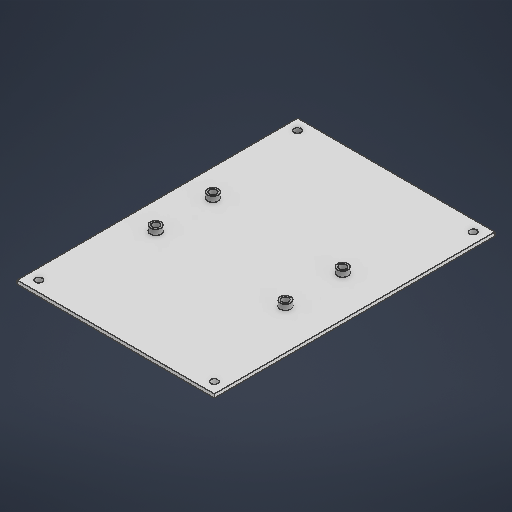
# Autodesk Inventor part: bottom
Saved by Autodesk Inventor 2026.2 (Build 302298010, 298A)
## iProperties
Created: 2026-05-12
Part Number: bottom
Material: 일반
Document SubType Name: Modeling
Designer: work
Density: 1 g/cm^3
Appearance: 기본값
Author: work
Autodesk Inventor part; units mm, degrees
ref_plane "YZ Plane" through (0, 0, 0) normal (1, 0, 0) x (0, 1, 0)
ref_plane "XZ Plane" through (0, 0, 0) normal (0, 1, 0) x (-1, 0, 0)
ref_plane "XY Plane" through (0, 0, 0) normal (0, 0, 1) x (1, 0, 0)
sketch "스케치1" plane through (0, 0, 0) normal (0, 1, 0) x (-1, 0, 0)
  line L0 (0, 0) -> (110, 0)
  line L1 (110, 0) -> (110, -156.5)
  line L2 (110, -156.5) -> (0, -156.5)
  line L3 (0, -156.5) -> (0, 0)
  line L4 (110, -78.25) -> (0, -78.25) construction
  line L5 (55, 0) -> (55, -156.5) construction
  line L6 (6, -6) -> (104, -6) construction
  line L7 (104, -6) -> (104, -150.5) construction
  line L8 (104, -150.5) -> (6, -150.5) construction
  line L9 (6, -150.5) -> (6, -6) construction
  line L10 (6, -6) -> (104, -150.5) construction
  line L11 (104, -6) -> (6, -150.5) construction
  line L12 (18.8, -43.25) -> (98.8, -43.25) construction
  line L13 (98.8, -43.25) -> (98.8, -113.25) construction
  line L14 (98.8, -113.25) -> (18.8, -113.25) construction
  line L15 (18.8, -113.25) -> (18.8, -43.25) construction
  line L16 (18.8, -43.25) -> (98.8, -113.25) construction
  line L17 (98.8, -43.25) -> (18.8, -113.25) construction
  line L18 (22.6, -62.25) -> (95, -62.25) construction
  line L19 (95, -62.25) -> (95, -94.25) construction
  line L20 (95, -94.25) -> (22.6, -94.25) construction
  line L21 (22.6, -94.25) -> (22.6, -62.25) construction
  line L22 (22.6, -62.25) -> (95, -94.25) construction
  line L23 (95, -62.25) -> (22.6, -94.25) construction
  circle A0 centre (95, -62.25) radius 2
  circle A1 centre (95, -94.25) radius 2
  circle A2 centre (22.6, -62.25) radius 2
  circle A3 centre (22.6, -94.25) radius 2
  circle A4 centre (6, -150.5) radius 2
  circle A5 centre (6, -6) radius 2
  circle A6 centre (104, -6) radius 2
  circle A7 centre (104, -150.5) radius 2
  point P0 (55, -78.25)
  point P1 (58.8, -78.25)
  dimension "d0" = 80
  dimension "d1" = 70
  dimension "d2" = 72.4
  dimension "d3" = 32
  dimension "d4" = 4
  dimension "d5" = 4
  dimension "d6" = 4
  dimension "d7" = 4
  dimension "d8" = 98
  dimension "d9" = 144.5
  dimension "d10" = 6
  dimension "d11" = 6
  dimension "d12" = 15
  dimension "d13" = 4
  dimension "d14" = 4
  dimension "d15" = 4
  dimension "d16" = 4
  constraints: 48 end point, 11 midpoint, 8 centre point, 8 coincident, 8 parallel, 4 horizontal, 4 perpendicular, 1 point on line
  measures "d0" distance of L13.end L14.end
  measures "d1" distance of L12.end L13.end
  measures "d2" distance of L19.end L20.end
  measures "d3" distance of L18.end L19.end
  measures "d4" diameter of A0
  measures "d5" diameter of A1
  measures "d6" diameter of A2
  measures "d7" diameter of A3
  measures "d8" distance between parallel lines of L9 L7
  measures "d9" distance of L8.end L6.start
  measures "d10" distance between parallel lines of L0 L6
  measures "d11" distance between parallel lines of L1 L7
  measures "d12" distance between parallel lines of L1 L19
  measures "d13" diameter of A4
  measures "d14" diameter of A5
  measures "d15" diameter of A6
  measures "d16" diameter of A7
extrude "돌출1" add sketch "스케치1" along normal blind 3
sketch "스케치2" plane through (0, 3, 0) normal (0, 1, 0) x (1, 0, 0)
  line L0 (0, 156.5) -> (-110, 156.5) projected
  line L1 (-110, 156.5) -> (-110, 0) projected
  line L2 (-110, 0) -> (0, 0) projected
  line L3 (0, 0) -> (0, 156.5) projected
  circle A0 centre (-104, 150.5) radius 2 projected
  circle A1 centre (-104, 6) radius 2 projected
  circle A2 centre (-6, 6) radius 2 projected
  circle A3 centre (-6, 150.5) radius 2 projected
  circle A4 centre (-22.6, 94.25) radius 2 projected
  circle A5 centre (-22.6, 62.25) radius 2 projected
  circle A6 centre (-95, 94.25) radius 2 projected
  circle A7 centre (-95, 62.25) radius 2 projected
  circle A8 centre (-95, 62.25) radius 3
  circle A9 centre (-95, 94.25) radius 3
  circle A10 centre (-22.6, 62.25) radius 3
  circle A11 centre (-22.6, 94.25) radius 3
  dimension "d19" = 6
  dimension "d20" = 6
  dimension "d21" = 6
  dimension "d22" = 6
  constraints: 4 centre point, 4 coincident
  measures "d19" diameter of A8
  measures "d20" diameter of A9
  measures "d21" diameter of A10
  measures "d22" diameter of A11
extrude "돌출2" add sketch "스케치2" along normal blind 3 contours A8 | A9 | A10 | A11
chamfer "모따기1" distance 1 angle 45 4 edges at (-55, 0, 0) (0, 0, -78.25) (-110, 0, -78.25) (-55, 0, -156.5)
